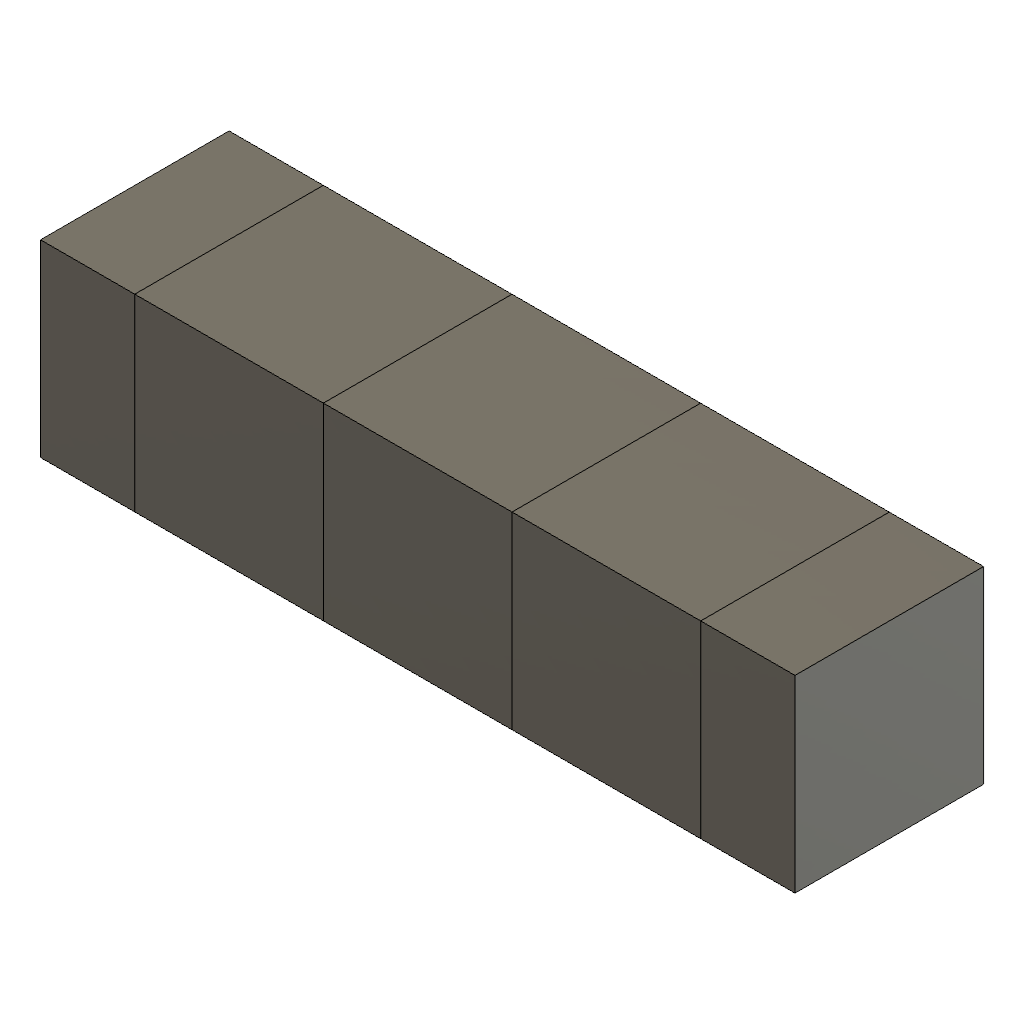
cut_multiple (Autodesk Fusion 360 design; units mm, degrees)
part number: 2026-10-20-20-56-07-926
Autodesk Fusion 360 part; units mm, degrees
sketch "Sketch1" plane through (0, 0, 0) normal (0, 0, 1) x (1, 0, 0)
  line L0 (0, 0) -> (80, 0)
  line L1 (80, 0) -> (80, 20)
  line L2 (80, 20) -> (0, 20)
  line L3 (0, 20) -> (0, 0)
extrude "Extrude1" add sketch "Sketch1" along normal blind 20 makes body 1
sketch "Sketch2" plane through (0, 0, 0) normal (0, 0, 1) x (1, 0, 0)
  line L0 (10, 0) -> (30, 0)
  line L1 (30, 0) -> (30, 20)
  line L2 (30, 20) -> (10, 20)
  line L3 (10, 20) -> (10, 0)
extrude "Extrude2" add sketch "Sketch2" along normal blind 20 separate body makes body 2
sketch "Sketch3" plane through (0, 0, 0) normal (0, 0, 1) x (1, 0, 0)
  line L0 (50, 0) -> (70, 0)
  line L1 (70, 0) -> (70, 20)
  line L2 (70, 20) -> (50, 20)
  line L3 (50, 20) -> (50, 0)
extrude "Extrude3" add sketch "Sketch3" along normal blind 20 separate body makes body 3
combine "ProbeCombine" operation cut target body 1 tool bodies 2 3 keep tools makes body 4 at (43.3333, 20, 6.6667) makes body 5 at (0, 13.3333, 6.6667)
named bodies: "TargetA", "ToolA", "ToolB", "TargetA (1)", "TargetA (2)"
